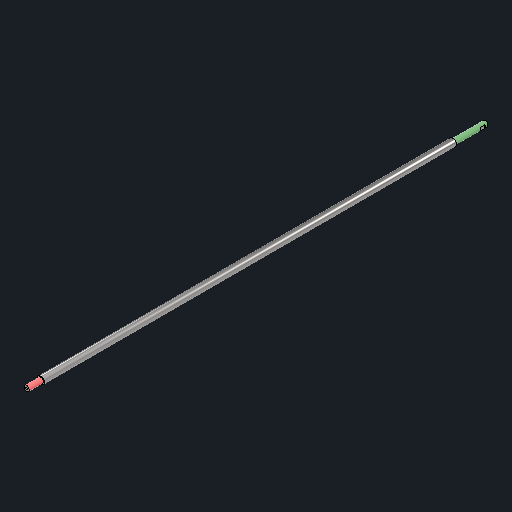
# Autodesk Inventor part: monotaro-TR16-machined-screw
Saved by Autodesk Inventor 2027.1 (Build 311270010, 270A)
## iProperties
Created: 2026-10-07
Part Number: monotaro-TR16-machined-screw
Material: Steel, Carbon
Document SubType Name: Modeling
Designer: queezz
Density: 7.85 g/cm^3
Appearance: Semi-Polished
Mass: 1506.46 g
Surface Area: 495.228 cm^2
Volume: 191.906 cm^3
Author: queezz
Autodesk Inventor part; units mm, degrees
sketch "Sketch1" plane through (0, 0, 0) normal (0, 0, 1) x (1, 0, 0)
  circle A0 centre (0, 0) radius 8
  dimension "d0" = 16
  constraints: 1 centre point, 1 coincident
  measures "d0" diameter of A0
extrude "Extrusion1" add sketch "Sketch1" along normal mid plane 1000
sketch "Sketch2" plane through (0, 0, -500) normal (0, 0, -1) x (-1, 0, 0)
  circle A0 centre (0, 0) radius 8 projected
  circle A1 centre (0, 0) radius 6
  dimension "d3" = 12
  constraints: 1 centre point, 1 coincident
  measures "d3" diameter of A1
extrude "Extrusion2" cut sketch "Sketch2" against normal blind 71
sketch "Sketch3" plane through (0, 0, 500) normal (0, 0, 1) x (1, 0, 0)
  circle A0 centre (0, 0) radius 6
  circle A1 centre (0, 0) radius 8 projected
  dimension "d6" = 12
  constraints: 1 centre point, 1 coincident
  measures "d6" diameter of A0
extrude "Extrusion3" cut sketch "Sketch3" against normal blind 31
ref_plane "Work Plane1" through (-1.3447, 4.8158, -489) normal (-0.2689, 0.9632, 0) x (-0.9632, -0.2689, 0)
sketch "Sketch4" plane through (-1.3447, 4.8158, -489) normal (-0.2689, 0.9632, 0) x (-0.9632, -0.2689, 0)
  line L0 (-7, -5) -> (7, -5)
  line L1 (7, -5) -> (7, 5)
  line L2 (7, 5) -> (-7, 5)
  line L3 (-7, 5) -> (-7, -5)
  constraints: 8 end point, 2 parallel, 1 horizontal, 1 perpendicular
extrude "Wheel hub set screw flat" [suppressed]
ref_plane "Work Plane2" through (0, 0, -500) normal (0, 0, 1) x (1, 0, 0)
sketch "Axial end pilot -50" plane through (0, 0, -500) normal (0, 0, 1) x (1, 0, 0)
  circle A0 centre (0, 0) radius 2.1
  constraints: 1 centre point
extrude "M5 axial retaining pilot -50" [suppressed]
ref_plane "Work Plane3" through (0, 0, 500) normal (0, 0, 1) x (1, 0, 0)
sketch "Axial end pilot 50" plane through (0, 0, 500) normal (0, 0, 1) x (1, 0, 0)
  circle A0 centre (0, 0) radius 2.1
  constraints: 1 centre point
extrude "M5 axial retaining pilot 50" cut sketch "Axial end pilot 50" against normal blind 10
ref_plane "Work Plane4" through (5, 0, -489) normal (1, 0, 0) x (0, 1, 0)
sketch "Sketch7" plane through (5, 0, -489) normal (1, 0, 0) x (0, 1, 0)
  line L0 (-7, -5) -> (7, -5)
  line L1 (7, -5) -> (7, 5)
  line L2 (7, 5) -> (-7, 5)
  line L3 (-7, 5) -> (-7, -5)
  constraints: 8 end point, 2 parallel, 1 horizontal, 1 perpendicular
extrude "Wheel journal flat 1 mm deep" cut sketch "Sketch7" along normal blind 2
body "Solid1"
